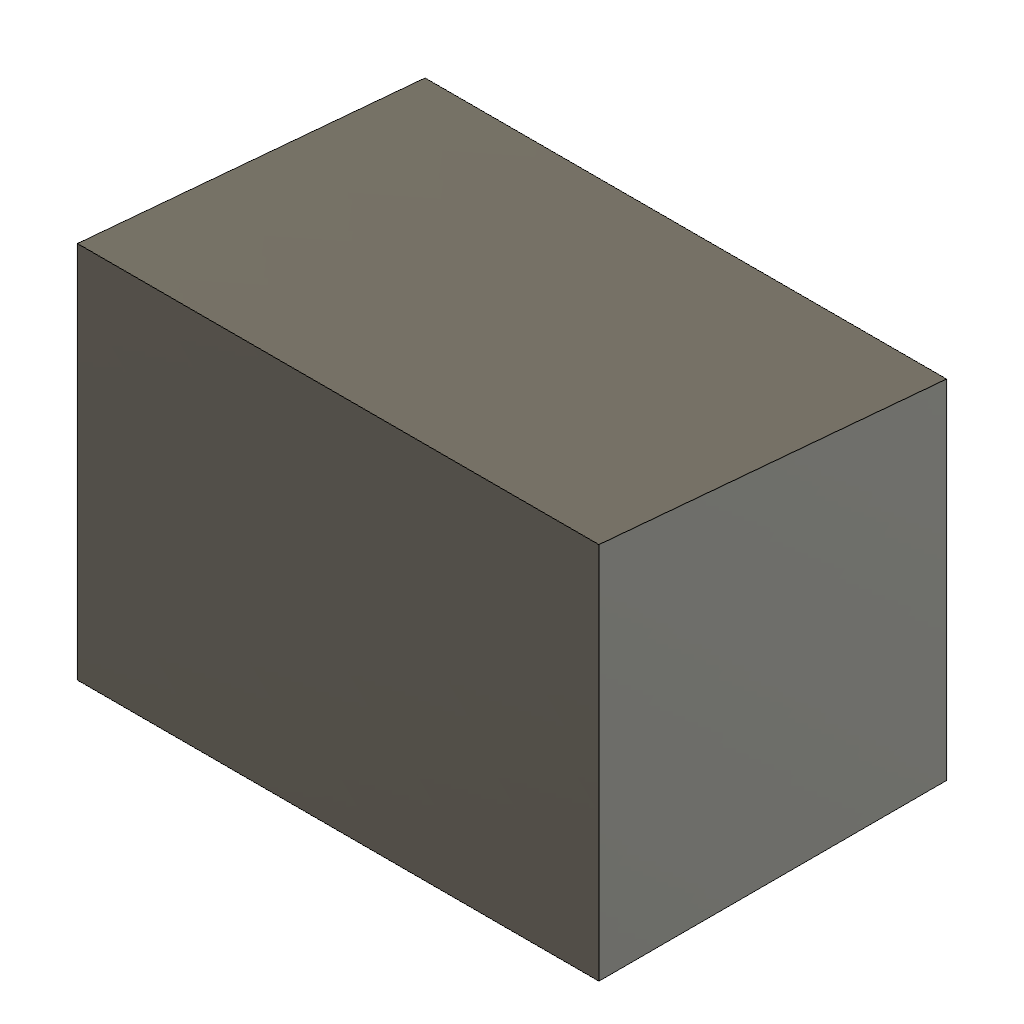
planar_face (Autodesk Fusion 360 design; units mm, degrees)
part number: 2026-10-20-21-03-02-110
Autodesk Fusion 360 part; units mm, degrees
sketch "Sketch1" plane through (0, 0, 0) normal (0, 0, 1) x (1, 0, 0)
  line L0 (0, 0) -> (30, 0)
  line L1 (30, 0) -> (30, 20)
  line L2 (30, 20) -> (0, 20)
  line L3 (0, 20) -> (0, 0)
extrude "SeedExtrusion" add sketch "Sketch1" along normal blind 20
draft "ProbeDraft" angle 5 neutral plane through (0, 0, 0) pull (0, 0, -1) 1 faces at (20, 20, 6.6667)
named bodies: "SeedBody"
